831002_P01_HARDWARE-STOP-WASHER_CAD (Autodesk Fusion 360 design; units mm, degrees)
description: HARDWARE - STOP WASHER - Ø10.5 X Ø20 X 1.5 - AL | Long đen chặn nhôm | rev P01 | UNITS MM; MATERIAL EN AW-5052-H32 SHEET 1.5; FINISH MILL, DEBURRED; ISO 2768-m; THICKNESS 1.50 +-0.05; laser cut, no drawing (D-89 part 4); joints register H-08; PROPOSED
part number: 831002
Autodesk Fusion 360 part; units mm, degrees
sketch "SKETCH - WASHER" plane through (0, 0, 0) normal (0, 0, 1) x (1, 0, 0)
  circle A0 centre (0, 0) radius 10
  circle A1 centre (0, 0) radius 5.25
  dimension "d6" = 20
  dimension "d7" = 10.5
  constraint coincident A0.centre A1.centre
  measures "d6" diameter of A0
  measures "d7" diameter of A1
extrude "EXTRUDE - WASHER" add sketch "SKETCH - WASHER" along normal blind 1.5
equation "seam_gap = 2.26 mm" comment "SKELETON P04 DECIDED: PM ruling 2026-10-31 (Mechanical Checker F-001, F-005): the Joints Engineer's 2.26 mm at all nine site seam types, set by a metal stop (1.5 stop washer + 0.76 rivnut head; joints register section 2.8)"
equation "rivnut_head = 0.76 mm" comment "SOURCE: Sherex CAH3-610-4.2 head 0.76 +-0.08 (joints register SHX)"
equation "wash_t = seam_gap - rivnut_head" comment "CALCULATION: the stop is the rivnut's head on this washer, so 2.26 - 0.76 = 1.5 (joints register 2.8)"
equation "wash_id = 10.5 mm" comment "PROPOSED: bore over the rivnut's body (9.50 max, SHX) (H-08)"
equation "wash_od = 20 mm" comment "PROPOSED: outside, on a 40 mm tube face (H-08)"
equation "d6 = wash_od"
equation "d7 = wash_id"
equation "d8 = wash_t"
named bodies: "STOP WASHER"
